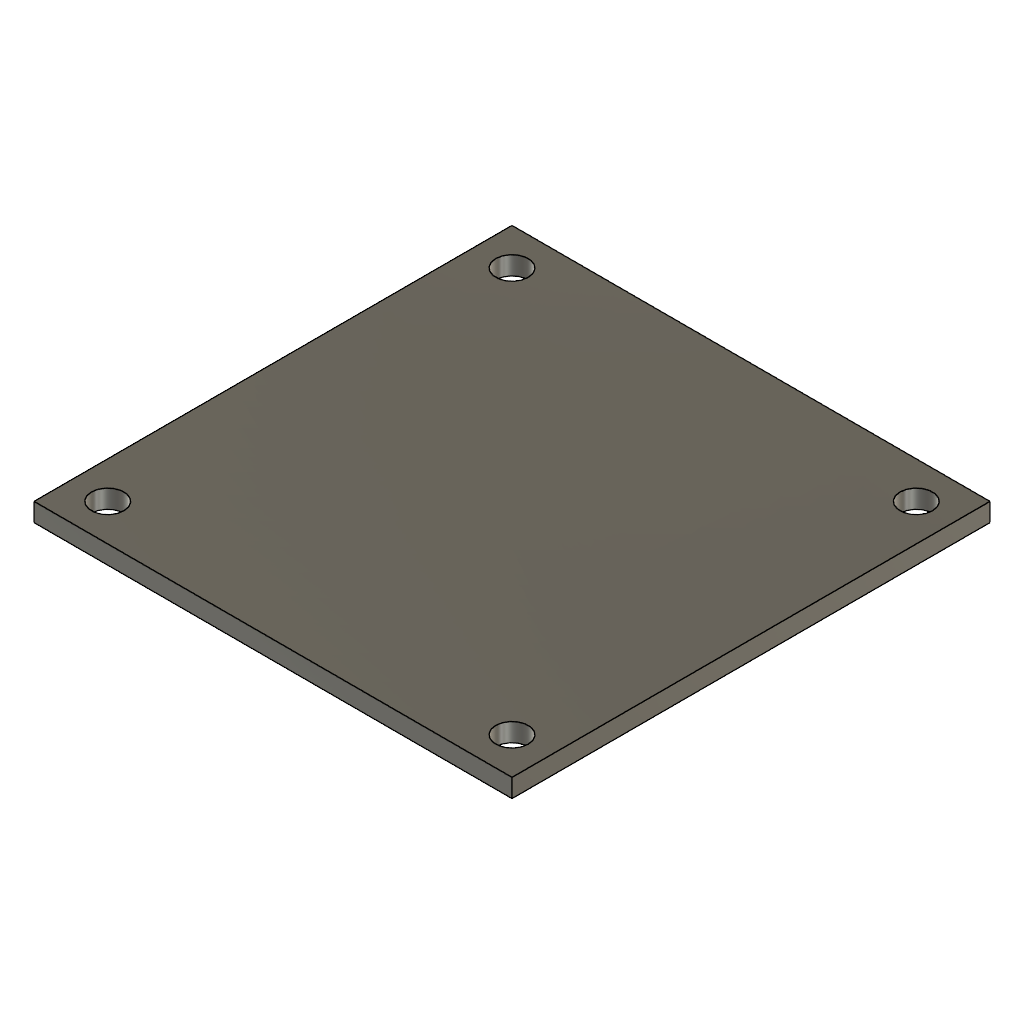
tensile-tester (Autodesk Fusion 360 archive; units mm, degrees)
design "Motor Bracket"
part number: 2026-11-15-13-29-55-198
Autodesk Fusion 360 part; units mm, degrees
sketch "Sketch1" plane through (0, 0, 0) normal (0, 0, 1) x (1, 0, 0)
  line L0 (34.8, 34.8) -> (-34.8, 34.8)
  line L1 (-34.8, 34.8) -> (-34.8, -34.8)
  line L2 (-34.8, -34.8) -> (34.8, -34.8)
  line L3 (34.8, -34.8) -> (34.8, 34.8)
  line L4 (34.8, 34.8) -> (-34.8, -34.8) construction
  line L5 (-34.8, 34.8) -> (34.8, -34.8) construction
  circle A0 centre (-34.8, 34.8) radius 2.8
  circle A1 centre (34.8, 34.8) radius 2.8
  circle A2 centre (34.8, -34.8) radius 2.8
  circle A3 centre (-34.8, -34.8) radius 2.8
  line L6 (-41.15, -41.15) -> (41.15, -41.15)
  line L7 (41.15, -41.15) -> (41.15, 41.15)
  line L8 (41.15, 41.15) -> (-41.15, 41.15)
  line L9 (-41.15, 41.15) -> (-41.15, -41.15)
  dimension "d1" = 69.6
  dimension "d2" = 69.6
  dimension "d3" = 5.6
  dimension "d4" = 5.6
  dimension "d5" = 5.6
  dimension "d6" = 5.6
  dimension "d7" = 6.35
  constraint horizontal L0
  constraint perpendicular L0 L1
  constraint parallel L0 L2
  constraint parallel L1 L3
  constraint coincident L4 origin
  constraint coincident L5 origin
  constraint coincident L0.end L1.start
  constraint coincident L0.start L3.end
  constraint coincident L2.end L3.start
  constraint coincident L1.end L2.start
  measures "d1" distance of L0.start L0.end
  measures "d2" distance of L0.start L2.end
  measures "d3" diameter of A0
  measures "d4" diameter of A1
  measures "d5" diameter of A2
  measures "d6" diameter of A3
extrude "Extrude1" add sketch "Sketch1" along normal blind 3.175 contours L0 L1 L2 L3 A0 A1 A2 A3 | L6 L7 L8 L9
sketch "Sketch2" plane through (0, 0, 3.175) normal (0, 0, 1) x (-1, 0, 0)
  circle A0 centre (34.8, -34.8) radius 2.8
  circle A1 centre (34.8, 34.8) radius 2.8
  circle A2 centre (-34.8, 34.8) radius 2.8
  circle A3 centre (-34.8, -34.8) radius 2.8
  line L0 (41.15, -41.15) -> (41.15, 41.15)
  line L1 (41.15, 41.15) -> (-41.15, 41.15)
  line L2 (-41.15, 41.15) -> (-41.15, -41.15)
  line L3 (-41.15, -41.15) -> (41.15, -41.15)
  line L4 (34.8, 34.8) -> (-34.8, -34.8) construction
  line L5 (34.8, -34.8) -> (-34.8, 34.8) construction
  line L6 (-11.3538, -11.3538) -> (11.3538, -11.3538)
  line L7 (11.3538, -11.3538) -> (11.3538, 11.3538)
  line L8 (11.3538, 11.3538) -> (-11.3538, 11.3538)
  line L9 (-11.3538, 11.3538) -> (-11.3538, -11.3538)
  line L10 (-11.3538, -11.3538) -> (11.3538, 11.3538) construction
  line L11 (11.3538, -11.3538) -> (-11.3538, 11.3538) construction
  circle A4 centre (0, 0) radius 6.35
  line L12 (-19.05, -19.05) -> (19.05, -19.05) construction
  line L13 (19.05, -19.05) -> (19.05, 19.05) construction
  line L14 (19.05, 19.05) -> (-19.05, 19.05) construction
  line L15 (-19.05, 19.05) -> (-19.05, -19.05) construction
  line L16 (-19.05, -19.05) -> (19.05, 19.05) construction
  line L17 (19.05, -19.05) -> (-19.05, 19.05) construction
  circle A5 centre (19.05, -19.05) radius 3.3
  circle A6 centre (-19.05, -19.05) radius 3.3
  circle A7 centre (19.05, 19.05) radius 3.3
  circle A8 centre (-19.05, 19.05) radius 3.3
  point P0 (11.3538, 0)
  dimension "d10" = 11.3538
  dimension "d37" = 12.7
  dimension "d54" = 38.1
  dimension "d55" = 6.6
  dimension "d56" = 6.6
  dimension "d57" = 6.6
  dimension "d58" = 6.6
  constraint coincident A1.centre L4.start
  constraint coincident A3.centre L4.end
  constraint coincident A0.centre L5.start
  constraint coincident A2.centre L5.end
  constraint horizontal L6
  constraint perpendicular L6 L7
  constraint parallel L6 L8
  constraint parallel L7 L9
  constraint coincident L10 A4.centre
  constraint coincident L11 A4.centre
  constraint coincident L4 L6.start
  constraint coincident A4.centre origin
  constraint midpoint L7 P0
  constraint horizontal L12
  constraint perpendicular L12 L13
  constraint parallel L12 L14
  constraint parallel L13 L15
  constraint coincident L16 A4.centre
  constraint coincident L17 A4.centre
  constraint coincident L4 L12.start
  constraint coincident L12.end L13.start
  constraint coincident L12.start L15.end
  constraint coincident L13.end L14.start
  constraint coincident L14.end L15.start
  measures "d10" distance of L6 A4.centre
  measures "d37" diameter of A4
  measures "d54" distance of L12.start L12.end
  measures "d55" diameter of A5
  measures "d56" diameter of A6
  measures "d57" diameter of A7
  measures "d58" diameter of A8

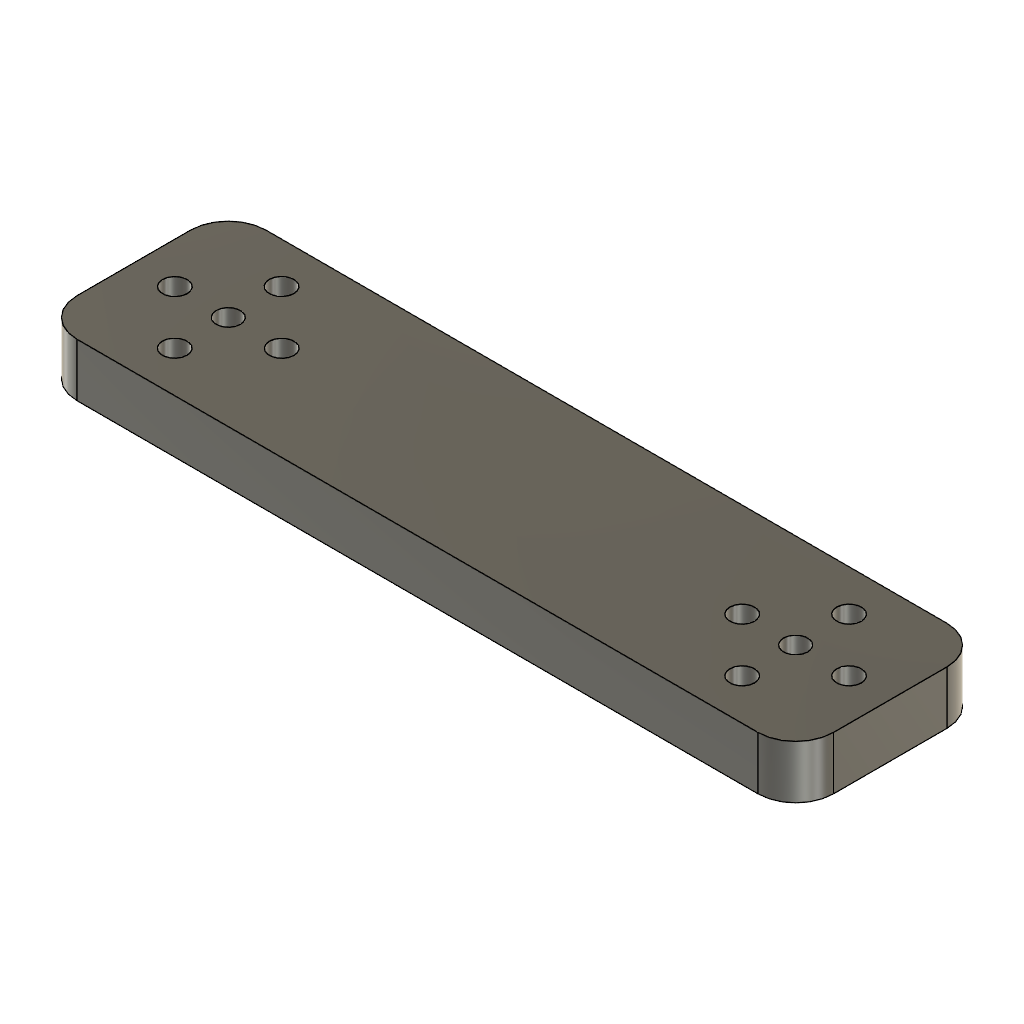
design "box"
part number: 2026-11-09-15-51-23-478
Autodesk Fusion 360 part; units mm, degrees
sketch "Sketch1" plane through (0, 0, 0) normal (0, 0, 1) x (1, 0, 0)
  line L0 (0, 2.54) -> (254, 2.54)
  line L1 (254, 2.54) -> (254, 53.34)
  line L2 (254, 53.34) -> (0, 53.34)
  line L3 (0, 53.34) -> (0, 2.54)
  constraint horizontal L0
  constraint vertical L1
  constraint horizontal L2
  constraint vertical L3
extrude "Extrude1" add sketch "Sketch1" along normal blind 14.303
sketch "Sketch2" plane through (0, 0, 14.303) normal (0, 0, 1) x (-1, 0, 0)
  line L0 (0, -53.34) -> (0, -2.54)
  line L1 (0, -2.54) -> (-254, -2.54)
  line L2 (-254, -2.54) -> (-254, -53.34)
  line L3 (-254, -53.34) -> (0, -53.34)
  line L4 (-50.8, -27.94) -> (-127, -27.94)
  line L5 (-127, -27.94) -> (-203.2, -27.94)
  point P0 (-127, -27.94)
  point P1 (-50.8, -27.94)
  point P2 (-203.2, -27.94)
  point P3 (-36.449, -27.94)
  point P4 (-50.7527, -13.5891)
  point P5 (-50.7527, -42.2909)
  point P6 (-217.551, -27.94)
  point P7 (-203.2, -42.291)
  point P8 (-203.2, -13.589)
  point P9 (-188.849, -27.94)
  point P10 (-65.151, -27.94)
  dimension "d5" = 76.2
  dimension "d14" = 14.351
  constraint coincident P1 L4.start
  constraint coincident P0 L4.end
  constraint coincident P2 L5.end
  constraint horizontal L5
  constraint equal L4 L5
  constraint coincident L5 P9
  constraint coincident L4 P10
  measures "d5" distance of P1 P0
  measures "d14" distance of P1 P3
hole "Hole1" at (50.8, 27.94, 14.303) at (203.2, 27.94, 14.303) at (203.2, 27.94, 14.303) direction (0, 0, -1) diameter 6.477 end through all
hole "Hole2" at (36.449, 27.94, 14.303) at (50.7527, 42.2909, 14.303) at (65.151, 27.94, 14.303) at (50.7527, 13.5891, 14.303) at (188.849, 27.94, 14.303) at (203.2, 42.291, 14.303) at (217.551, 27.94, 14.303) at (203.2, 13.589, 14.303) direction (0, 0, -1) diameter 6.604 depth 6.7564 tip angle 180
fillet "Fillet1" radius 10.16 4 edges at (254, 2.54, 7.1515) (254, 53.34, 7.1515) (0, 2.54, 7.1515) (0, 53.34, 7.1515)
sketch "Sketch3" plane through (0, 0, 14.303) normal (0, 0, 1) x (-1, 0, 0)
  line L0 (-50.8, -27.94) -> (-127, -27.94)
  line L1 (-127.0134, -37.84) -> (-127.0134, -16.7936) construction
  line L2 (-25.4, 6.2939) -> (12.6979, 6.2939)
  line L3 (12.6979, 6.2939) -> (12.6979, -62.1739)
  line L4 (12.6979, -62.1739) -> (-25.4, -62.1739)
  line L5 (-25.4, -62.1739) -> (-25.4, 6.2939)
  line L6 (-228.6268, -62.1739) -> (-228.6268, 6.2939)
  line L7 (-228.6268, 6.2939) -> (-266.7247, 6.2939)
  line L8 (-266.7247, 6.2939) -> (-266.7247, -62.1739)
  line L9 (-266.7247, -62.1739) -> (-228.6268, -62.1739)
  point P0 (-127, -27.94)
  point P1 (-25.4, -27.94)
  dimension "d29" = 101.6
  constraint perpendicular L0 L1
  constraint horizontal L2
  constraint vertical L3
  constraint horizontal L4
  constraint vertical L5
  constraint midpoint L5 P1
  constraint horizontal P0 P1
  constraint symmetric L1 L2.start L6.end
  constraint symmetric L1 L2.end L7.end
  constraint symmetric L1 L3.end L8.end
  constraint symmetric L1 L4.end L6.start
  measures "d29" distance of P0 P1
extrude "Extrude3" cut sketch "Sketch3" against normal blind 25.4
fillet "Fillet3" radius 10.16 4 edges at (25.4, 53.34, 7.1515) (25.4, 2.54, 7.1515) (228.6268, 2.54, 7.1515) (228.6268, 53.34, 7.1515)
equation "h = ( ( ( w * length ^ 3 ) / ( 32 * e * def * depth ) ) ^ ( 1 / 3 ) ) * 1 in"
equation "L = 10 in"
equation "D = 2 in"
equation "def = ( 0.00393701 in ) / in"
equation "SF = 4"
equation "e = ( 9993.1 ksi ) / ksi"
equation "w = 0.4496"
equation "length = ( 10 in ) / in"
equation "depth = ( 2 in ) / in"

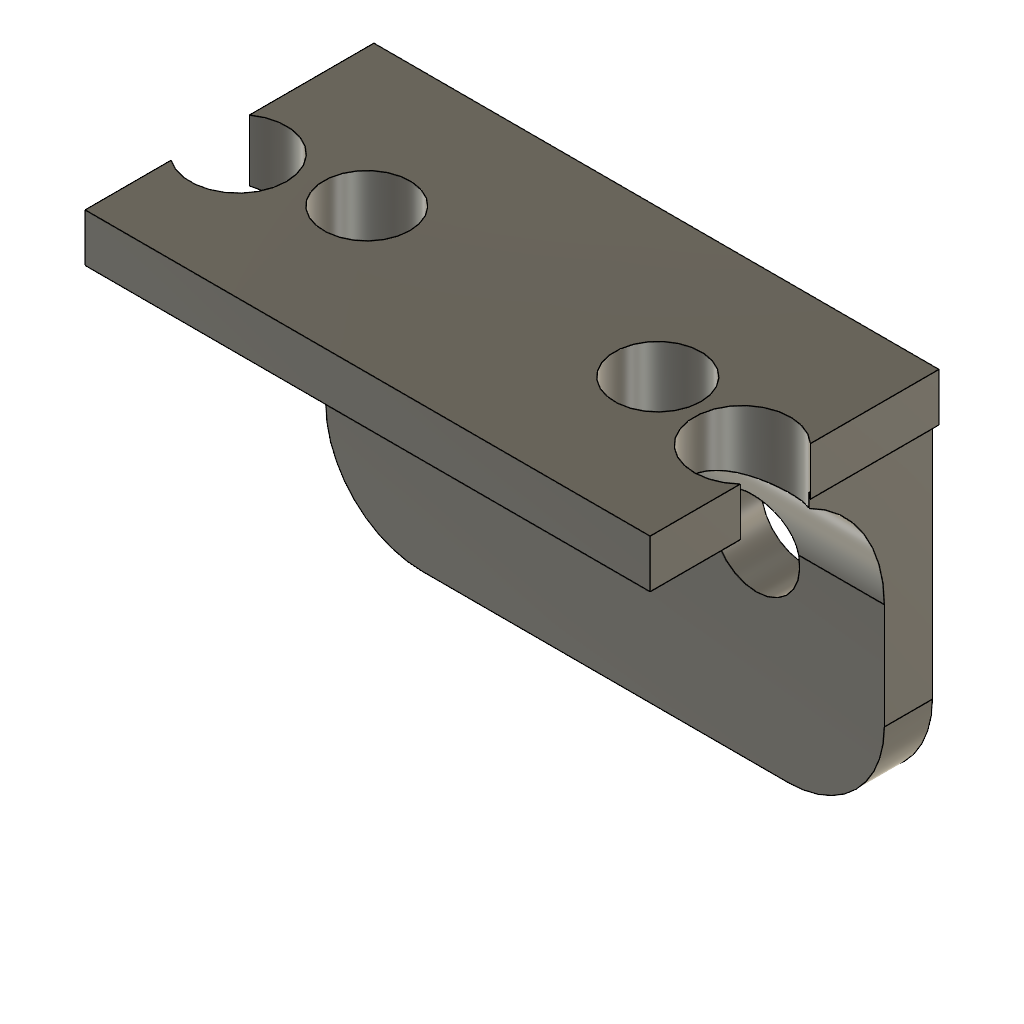
design "connector"
part number: 2026-11-18-19-07-47-330
Autodesk Fusion 360 part; units mm, degrees
sketch "Sketch1" plane through (0, 0, 0) normal (0, 1, 0) x (1, 0, 0)
  line L0 (12.7, 0) -> (60.96, 0)
  line L1 (73.66, -12.7) -> (73.66, -50.8)
  line L2 (73.66, -50.8) -> (0, -50.8)
  line L3 (0, -50.8) -> (0, -12.7)
  line L4 (12.4206, -50.8) -> (12.4206, 0) construction
  line L5 (23.7998, -50.8) -> (23.7998, 0) construction
  line L6 (51.1302, -50.8) -> (51.1302, 0) construction
  line L7 (62.5094, -50.8) -> (62.5094, 0) construction
  circle A0 centre (18.3023, -25.4) radius 5.8817
  circle A1 centre (56.796, -25.4) radius 5.7134
  line L8 (18.3023, -25.4) -> (18.3023, -50.8) construction
  line L9 (56.796, -25.4) -> (56.796, -50.8) construction
  arc A2 (73.66, -12.7) -> (60.96, 0) centre (60.96, -12.7) ccw
  arc A3 (12.7, 0) -> (0, -12.7) centre (12.7, -12.7) ccw
  point P0 (73.66, 0)
  dimension "d1" = 73.66
  dimension "d2" = 50.8
  dimension "d4" = 11.3792
  dimension "d6" = 11.3792
  dimension "d7" = 25.4
  dimension "d9" = 25.4
  dimension "d10" = 12.7
  dimension "d11" = 12.4206
  dimension "d12" = 51.1302
  dimension "d13" = 12.7
  constraint horizontal L0
  constraint vertical L1
  constraint horizontal L2
  constraint vertical L3
  constraint tangent L4 A0
  constraint tangent L7 A1
  constraint coincident A0.centre L8.start
  constraint coincident L2 L8.end
  constraint perpendicular L2 L8
  constraint coincident A1.centre L9.start
  constraint coincident L2 L9.end
  constraint perpendicular L2 L9
  constraint coincident P0 L0
  constraint coincident P0 L1
  constraint tangent L0 A2
  constraint tangent L1 A2
  constraint coincident origin L0
  constraint coincident origin L3
  constraint tangent L0 A3
  constraint tangent L3 A3
  measures "d1" distance of origin P0
  measures "d2" distance of origin L2.end
  measures "d7" distance of A1.centre L9.end
  measures "d9" distance of A0.centre L8.end
  measures "d10" radius of A2
  measures "d11" distance of L3 L4
  measures "d12" distance of L3 L6
  measures "d13" radius of A3
extrude "Extrude1" add sketch "Sketch1" along normal blind 6.35
chamfer "Chamfer1" distance 1.27 angle 45 1 edges at (36.83, 6.35, 50.8) tangent chain off
sketch "Sketch2" plane through (0, 0, 50.8) normal (0, 0, 1) x (-1, 0, 0)
  line L0 (-73.66, -5.08) -> (0, -5.08)
  line L1 (0, -5.08) -> (0, 0)
  line L2 (0, 0) -> (-73.66, 0)
  line L3 (-73.66, 0) -> (-73.66, -5.08)
  line L4 (0, -6.35) -> (-74.5244, -6.35)
  line L5 (-74.5244, 31.75) -> (0, 31.75)
  circle A0 centre (-70.1741, 15.24) radius 6.35
  circle A1 centre (-3.701, 15.24) radius 6.35
  line L6 (0, 31.75) -> (0, 20.3999)
  line L7 (0, 10.0801) -> (0, -6.35)
  line L8 (-74.5244, -6.35) -> (-74.5244, 10.6142)
  line L9 (-74.5244, 19.8658) -> (-74.5244, 31.75)
  line L10 (-70.1741, 15.24) -> (-70.1741, 0) construction
  line L11 (-3.701, 15.24) -> (-3.701, 0) construction
  line L12 (0, 31.75) -> (0, -6.35) construction
  line L13 (-12.4206, 31.75) -> (-12.4206, -6.35) construction
  line L14 (-23.7998, 31.75) -> (-23.7998, -6.35) construction
  line L15 (-51.1302, 31.75) -> (-51.1302, -6.35) construction
  line L16 (-62.5094, 31.75) -> (-62.5094, -6.35) construction
  circle A2 centre (-56.8198, 13.0343) radius 5.6994
  circle A3 centre (-18.1102, 12.7) radius 5.6896
  dimension "d17" = 38.1
  dimension "d19" = 12.7
  dimension "d20" = 12.7
  dimension "d26" = 15.24
  dimension "d27" = 15.24
  dimension "d28" = 12.4206
  dimension "d29" = 11.3792
  dimension "d30" = 51.1302
  dimension "d31" = 11.3792
  constraint horizontal L4
  constraint vertical L8
  constraint horizontal L5
  constraint vertical L6
  constraint coincident A1 L6.end
  constraint coincident A1 L7.start
  constraint collinear L6 L7
  constraint coincident A0 L8.end
  constraint coincident A0 L9.start
  constraint collinear L8 L9
  constraint coincident A0.centre L10.start
  constraint coincident L2 L10.end
  constraint perpendicular L2 L10
  constraint coincident A1.centre L11.start
  constraint coincident L2 L11.end
  constraint perpendicular L2 L11
  constraint tangent L13 A3
  measures "d17" distance of L4.start L5.end
  measures "d19" diameter of A0
  measures "d20" diameter of A1
  measures "d26" distance of A0.centre L10.end
  measures "d27" distance of A1.centre L11.end
extrude "Extrude2" add sketch "Sketch2" against normal blind 6.35 contours L0 L2 L3 L4 L5 A0 A1 L6 L7 L8 L9
fillet "Fillet1" radius 17.78 1 edges at (36.83, 0, 44.45)
